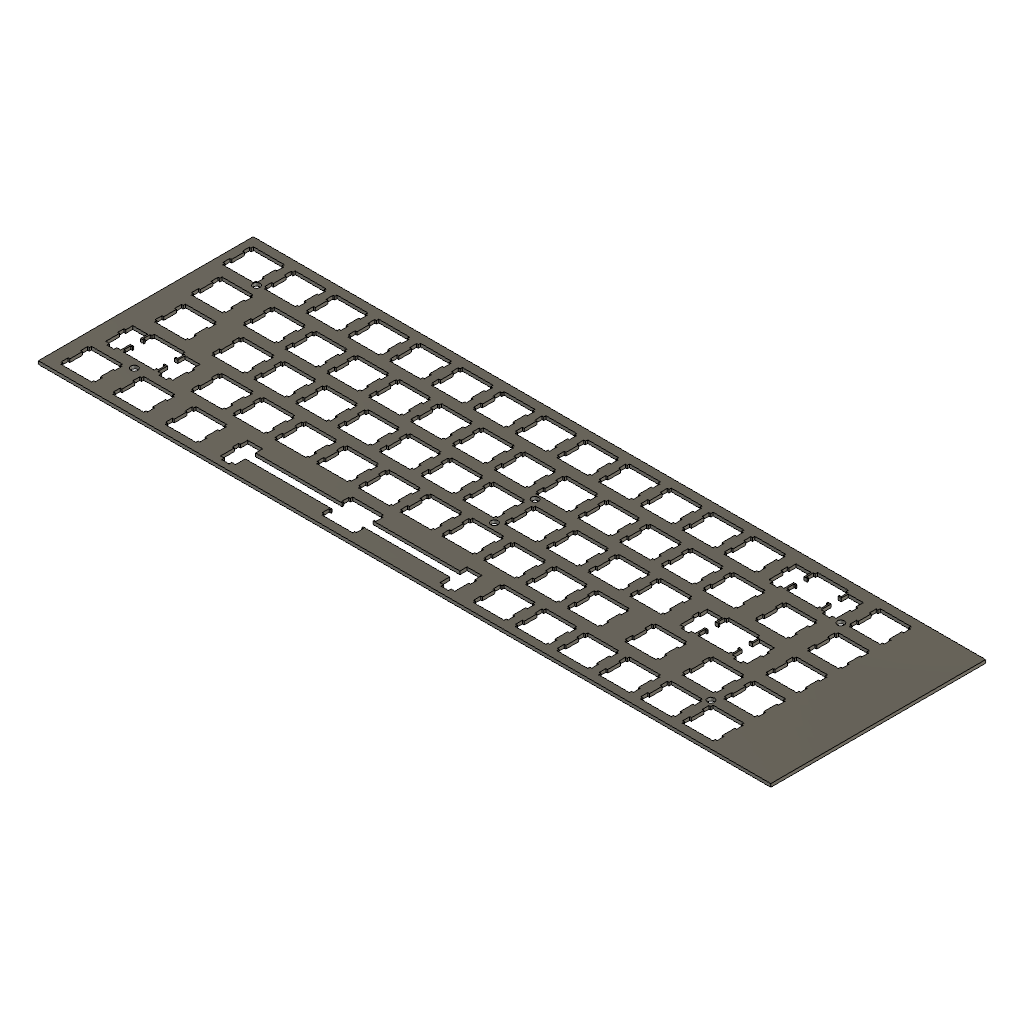
kaze-plate (Autodesk Fusion 360 design; units mm, degrees)
part number: 2026-10-22-08-37-23-062
Autodesk Fusion 360 part; units mm, degrees
(part 1 of 2)
sketch "Sketch1" plane through (0, 0, 0) normal (0, 0, 1) x (1, 0, 0)
  line L0 (-60, 50) -> (274, 50)
  line L1 (274, 50) -> (274, -48)
  line L2 (274, -48) -> (-60, -48)
  line L3 (-60, -48) -> (-60, 50)
  line L4 (65.562, -30.2169) -> (65.562, -31.2173)
  line L5 (65.562, -31.2173) -> (64.763, -31.2173)
  line L6 (64.763, -31.2173) -> (64.763, -34.3152)
  line L7 (64.763, -34.3152) -> (65.562, -34.3152)
  line L8 (65.562, -34.3152) -> (65.562, -34.9174)
  line L9 (65.562, -34.9174) -> (25.9381, -34.9174)
  line L10 (25.9381, -34.9174) -> (25.9381, -31.6872)
  line L11 (25.9381, -31.6872) -> (19.187, -31.6872)
  line L12 (19.187, -31.6872) -> (19.187, -34.9174)
  line L13 (19.187, -34.9174) -> (18.3629, -34.9174)
  line L14 (18.3629, -34.9174) -> (18.3629, -37.7162)
  line L15 (18.3629, -37.7162) -> (19.187, -37.7162)
  line L16 (19.187, -37.7162) -> (19.187, -43.9862)
  line L17 (19.187, -43.9862) -> (20.912, -43.9862)
  line L18 (20.912, -43.9862) -> (20.912, -45.1865)
  line L19 (20.912, -45.1865) -> (24.2126, -45.1865)
  line L20 (24.2126, -45.1865) -> (24.2126, -43.9862)
  line L21 (24.2126, -43.9862) -> (25.9381, -43.9862)
  line L22 (25.9381, -43.9862) -> (25.9381, -39.5159)
  line L23 (25.9381, -39.5159) -> (65.562, -39.5159)
  line L24 (65.562, -39.5159) -> (65.562, -40.1167)
  line L25 (65.562, -40.1167) -> (64.763, -40.1167)
  line L26 (64.763, -40.1167) -> (64.763, -43.2173)
  line L27 (64.763, -43.2173) -> (65.562, -43.2173)
  line L28 (65.562, -43.2173) -> (65.562, -44.2164)
  line L29 (65.562, -44.2164) -> (79.563, -44.2164)
  line L30 (79.563, -44.2164) -> (79.563, -43.2173)
  line L31 (79.563, -43.2173) -> (80.362, -43.2173)
  line L32 (80.362, -43.2173) -> (80.362, -40.1167)
  line L33 (80.362, -40.1167) -> (79.563, -40.1167)
  line L34 (79.563, -40.1167) -> (79.563, -39.5159)
  line L35 (79.563, -39.5159) -> (119.187, -39.5159)
  line L36 (119.187, -39.5159) -> (119.187, -43.9862)
  line L37 (119.187, -43.9862) -> (120.912, -43.9862)
  line L38 (120.912, -43.9862) -> (120.912, -45.1865)
  line L39 (120.912, -45.1865) -> (124.213, -45.1865)
  line L40 (124.213, -45.1865) -> (124.213, -43.9862)
  line L41 (124.213, -43.9862) -> (125.938, -43.9862)
  line L42 (125.938, -43.9862) -> (125.938, -37.7162)
  line L43 (125.938, -37.7162) -> (126.762, -37.7162)
  line L44 (126.762, -37.7162) -> (126.762, -34.9174)
  line L45 (126.762, -34.9174) -> (125.938, -34.9174)
  line L46 (125.938, -34.9174) -> (125.938, -31.6872)
  line L47 (125.938, -31.6872) -> (119.187, -31.6872)
  line L48 (119.187, -31.6872) -> (119.187, -34.9174)
  line L49 (119.187, -34.9174) -> (79.563, -34.9174)
  line L50 (79.563, -34.9174) -> (79.563, -34.3152)
  line L51 (79.563, -34.3152) -> (80.362, -34.3152)
  line L52 (80.362, -34.3152) -> (80.362, -31.2173)
  line L53 (80.362, -31.2173) -> (79.563, -31.2173)
  line L54 (79.563, -31.2173) -> (79.563, -30.2169)
  line L55 (79.563, -30.2169) -> (65.562, -30.2169)
  line L56 (-53.4991, -30.2169) -> (-53.4991, -31.2173)
  line L57 (-53.4991, -31.2173) -> (-54.2997, -31.2173)
  line L58 (-54.2997, -31.2173) -> (-54.2997, -34.3152)
  line L59 (-54.2997, -34.3152) -> (-53.4991, -34.3152)
  line L60 (-53.4991, -34.3152) -> (-53.4991, -40.1167)
  line L61 (-53.4991, -40.1167) -> (-54.2997, -40.1167)
  line L62 (-54.2997, -40.1167) -> (-54.2997, -43.2173)
  line L63 (-54.2997, -43.2173) -> (-53.4991, -43.2173)
  line L64 (-53.4991, -43.2173) -> (-53.4991, -44.2164)
  line L65 (-53.4991, -44.2164) -> (-39.4996, -44.2164)
  line L66 (-39.4996, -44.2164) -> (-39.4996, -43.2173)
  line L67 (-39.4996, -43.2173) -> (-38.699, -43.2173)
  line L68 (-38.699, -43.2173) -> (-38.699, -40.1167)
  line L69 (-38.699, -40.1167) -> (-39.4996, -40.1167)
  line L70 (-39.4996, -40.1167) -> (-39.4996, -34.3152)
  line L71 (-39.4996, -34.3152) -> (-38.699, -34.3152)
  line L72 (-38.699, -34.3152) -> (-38.699, -31.2173)
  line L73 (-38.699, -31.2173) -> (-39.4996, -31.2173)
  line L74 (-39.4996, -31.2173) -> (-39.4996, -30.2169)
  line L75 (-39.4996, -30.2169) -> (-53.4991, -30.2169)
  line L76 (-29.688, -30.2169) -> (-29.688, -31.2173)
  line L77 (-29.688, -31.2173) -> (-30.4872, -31.2173)
  line L78 (-30.4872, -31.2173) -> (-30.4872, -34.3152)
  line L79 (-30.4872, -34.3152) -> (-29.688, -34.3152)
  line L80 (-29.688, -34.3152) -> (-29.688, -40.1167)
  line L81 (-29.688, -40.1167) -> (-30.4872, -40.1167)
  line L82 (-30.4872, -40.1167) -> (-30.4872, -43.2173)
  line L83 (-30.4872, -43.2173) -> (-29.688, -43.2173)
  line L84 (-29.688, -43.2173) -> (-29.688, -44.2164)
  line L85 (-29.688, -44.2164) -> (-15.6872, -44.2164)
  line L86 (-15.6872, -44.2164) -> (-15.6872, -43.2173)
  line L87 (-15.6872, -43.2173) -> (-14.8878, -43.2173)
  line L88 (-14.8878, -43.2173) -> (-14.8878, -40.1167)
  line L89 (-14.8878, -40.1167) -> (-15.6872, -40.1167)
  line L90 (-15.6872, -40.1167) -> (-15.6872, -34.3152)
  line L91 (-15.6872, -34.3152) -> (-14.8878, -34.3152)
  line L92 (-14.8878, -34.3152) -> (-14.8878, -31.2173)
  line L93 (-14.8878, -31.2173) -> (-15.6872, -31.2173)
  line L94 (-15.6872, -31.2173) -> (-15.6872, -30.2169)
  line L95 (-15.6872, -30.2169) -> (-29.688, -30.2169)
  line L96 (-5.874, -30.2169) -> (-5.874, -31.2173)
  line L97 (-5.874, -31.2173) -> (-6.6748, -31.2173)
  line L98 (-6.6748, -31.2173) -> (-6.6748, -34.3152)
  line L99 (-6.6748, -34.3152) -> (-5.874, -34.3152)
  line L100 (-5.874, -34.3152) -> (-5.874, -40.1167)
  line L101 (-5.874, -40.1167) -> (-6.6748, -40.1167)
  line L102 (-6.6748, -40.1167) -> (-6.6748, -43.2173)
  line L103 (-6.6748, -43.2173) -> (-5.874, -43.2173)
  line L104 (-5.874, -43.2173) -> (-5.874, -44.2164)
  line L105 (-5.874, -44.2164) -> (8.1253, -44.2164)
  line L106 (8.1253, -44.2164) -> (8.1253, -43.2173)
  line L107 (8.1253, -43.2173) -> (8.9261, -43.2173)
  line L108 (8.9261, -43.2173) -> (8.9261, -40.1167)
  line L109 (8.9261, -40.1167) -> (8.1253, -40.1167)
  line L110 (8.1253, -40.1167) -> (8.1253, -34.3152)
  line L111 (8.1253, -34.3152) -> (8.9261, -34.3152)
  line L112 (8.9261, -34.3152) -> (8.9261, -31.2173)
  line L113 (8.9261, -31.2173) -> (8.1253, -31.2173)
  line L114 (8.1253, -31.2173) -> (8.1253, -30.2169)
  line L115 (8.1253, -30.2169) -> (-5.874, -30.2169)
  line L116 (134.62, -30.2169) -> (134.62, -31.2173)
  line L117 (134.62, -31.2173) -> (133.819, -31.2173)
  line L118 (133.819, -31.2173) -> (133.819, -34.3152)
  line L119 (133.819, -34.3152) -> (134.62, -34.3152)
  line L120 (134.62, -34.3152) -> (134.62, -40.1167)
  line L121 (134.62, -40.1167) -> (133.819, -40.1167)
  line L122 (133.819, -40.1167) -> (133.819, -43.2173)
  line L123 (133.819, -43.2173) -> (134.62, -43.2173)
  line L124 (134.62, -43.2173) -> (134.62, -44.2164)
  line L125 (134.62, -44.2164) -> (148.619, -44.2164)
  line L126 (148.619, -44.2164) -> (148.619, -43.2173)
  line L127 (148.619, -43.2173) -> (149.42, -43.2173)
  line L128 (149.42, -43.2173) -> (149.42, -40.1167)
  line L129 (149.42, -40.1167) -> (148.619, -40.1167)
  line L130 (148.619, -40.1167) -> (148.619, -34.3152)
  line L131 (148.619, -34.3152) -> (149.42, -34.3152)
  line L132 (149.42, -34.3152) -> (149.42, -31.2173)
  line L133 (149.42, -31.2173) -> (148.619, -31.2173)
  line L134 (148.619, -31.2173) -> (148.619, -30.2169)
  line L135 (148.619, -30.2169) -> (134.62, -30.2169)
  line L136 (153.67, -30.2169) -> (153.67, -31.2173)
  line L137 (153.67, -31.2173) -> (152.869, -31.2173)
  line L138 (152.869, -31.2173) -> (152.869, -34.3152)
  line L139 (152.869, -34.3152) -> (153.67, -34.3152)
  line L140 (153.67, -34.3152) -> (153.67, -40.1167)
  line L141 (153.67, -40.1167) -> (152.869, -40.1167)
  line L142 (152.869, -40.1167) -> (152.869, -43.2173)
  line L143 (152.869, -43.2173) -> (153.67, -43.2173)
  line L144 (153.67, -43.2173) -> (153.67, -44.2164)
  line L145 (153.67, -44.2164) -> (167.669, -44.2164)
  line L146 (167.669, -44.2164) -> (167.669, -43.2173)
  line L147 (167.669, -43.2173) -> (168.47, -43.2173)
  line L148 (168.47, -43.2173) -> (168.47, -40.1167)
  line L149 (168.47, -40.1167) -> (167.669, -40.1167)
  line L150 (167.669, -40.1167) -> (167.669, -34.3152)
  line L151 (167.669, -34.3152) -> (168.47, -34.3152)
  line L152 (168.47, -34.3152) -> (168.47, -31.2173)
  line L153 (168.47, -31.2173) -> (167.669, -31.2173)
  line L154 (167.669, -31.2173) -> (167.669, -30.2169)
  line L155 (167.669, -30.2169) -> (153.67, -30.2169)
  line L156 (172.72, -30.2169) -> (172.72, -31.2173)
  line L157 (172.72, -31.2173) -> (171.919, -31.2173)
  line L158 (171.919, -31.2173) -> (171.919, -34.3152)
  line L159 (171.919, -34.3152) -> (172.72, -34.3152)
  line L160 (172.72, -34.3152) -> (172.72, -40.1167)
  line L161 (172.72, -40.1167) -> (171.919, -40.1167)
  line L162 (171.919, -40.1167) -> (171.919, -43.2173)
  line L163 (171.919, -43.2173) -> (172.72, -43.2173)
  line L164 (172.72, -43.2173) -> (172.72, -44.2164)
  line L165 (172.72, -44.2164) -> (186.719, -44.2164)
  line L166 (186.719, -44.2164) -> (186.719, -43.2173)
  line L167 (186.719, -43.2173) -> (187.52, -43.2173)
  line L168 (187.52, -43.2173) -> (187.52, -40.1167)
  line L169 (187.52, -40.1167) -> (186.719, -40.1167)
  line L170 (186.719, -40.1167) -> (186.719, -34.3152)
  line L171 (186.719, -34.3152) -> (187.52, -34.3152)
  line L172 (187.52, -34.3152) -> (187.52, -31.2173)
  line L173 (187.52, -31.2173) -> (186.719, -31.2173)
  line L174 (186.719, -31.2173) -> (186.719, -30.2169)
  line L175 (186.719, -30.2169) -> (172.72, -30.2169)
  line L176 (191.77, -30.2169) -> (191.77, -31.2173)
  line L177 (191.77, -31.2173) -> (190.969, -31.2173)
  line L178 (190.969, -31.2173) -> (190.969, -34.3152)
  line L179 (190.969, -34.3152) -> (191.77, -34.3152)
  line L180 (191.77, -34.3152) -> (191.77, -40.1167)
  line L181 (191.77, -40.1167) -> (190.969, -40.1167)
  line L182 (190.969, -40.1167) -> (190.969, -43.2173)
  line L183 (190.969, -43.2173) -> (191.77, -43.2173)
  line L184 (191.77, -43.2173) -> (191.77, -44.2164)
  line L185 (191.77, -44.2164) -> (205.769, -44.2164)
  line L186 (205.769, -44.2164) -> (205.769, -43.2173)
  line L187 (205.769, -43.2173) -> (206.57, -43.2173)
  line L188 (206.57, -43.2173) -> (206.57, -40.1167)
  line L189 (206.57, -40.1167) -> (205.769, -40.1167)
  line L190 (205.769, -40.1167) -> (205.769, -34.3152)
  line L191 (205.769, -34.3152) -> (206.57, -34.3152)
  line L192 (206.57, -34.3152) -> (206.57, -31.2173)
  line L193 (206.57, -31.2173) -> (205.769, -31.2173)
  line L194 (205.769, -31.2173) -> (205.769, -30.2169)
  line L195 (205.769, -30.2169) -> (191.77, -30.2169)
  line L196 (210.82, -30.2169) -> (210.82, -31.2173)
  line L197 (210.82, -31.2173) -> (210.019, -31.2173)
  line L198 (210.019, -31.2173) -> (210.019, -34.3152)
  line L199 (210.019, -34.3152) -> (210.82, -34.3152)
  line L200 (210.82, -34.3152) -> (210.82, -40.1167)
  line L201 (210.82, -40.1167) -> (210.019, -40.1167)
  line L202 (210.019, -40.1167) -> (210.019, -43.2173)
  line L203 (210.019, -43.2173) -> (210.82, -43.2173)
  line L204 (210.82, -43.2173) -> (210.82, -44.2164)
  line L205 (210.82, -44.2164) -> (224.819, -44.2164)
  line L206 (224.819, -44.2164) -> (224.819, -43.2173)
  line L207 (224.819, -43.2173) -> (225.62, -43.2173)
  line L208 (225.62, -43.2173) -> (225.62, -40.1167)
  line L209 (225.62, -40.1167) -> (224.819, -40.1167)
  line L210 (224.819, -40.1167) -> (224.819, -34.3152)
  line L211 (224.819, -34.3152) -> (225.62, -34.3152)
  line L212 (225.62, -34.3152) -> (225.62, -31.2173)
  line L213 (225.62, -31.2173) -> (224.819, -31.2173)
  line L214 (224.819, -31.2173) -> (224.819, -30.2169)
  line L215 (224.819, -30.2169) -> (210.82, -30.2169)
  line L216 (229.87, -30.2169) -> (229.87, -31.2173)
  line L217 (229.87, -31.2173) -> (229.069, -31.2173)
  line L218 (229.069, -31.2173) -> (229.069, -34.3152)
  line L219 (229.069, -34.3152) -> (229.87, -34.3152)
  line L220 (229.87, -34.3152) -> (229.87, -40.1167)
  line L221 (229.87, -40.1167) -> (229.069, -40.1167)
  line L222 (229.069, -40.1167) -> (229.069, -43.2173)
  line L223 (229.069, -43.2173) -> (229.87, -43.2173)
  line L224 (229.87, -43.2173) -> (229.87, -44.2164)
  line L225 (229.87, -44.2164) -> (243.869, -44.2164)
  line L226 (243.869, -44.2164) -> (243.869, -43.2173)
  line L227 (243.869, -43.2173) -> (244.67, -43.2173)
  line L228 (244.67, -43.2173) -> (244.67, -40.1167)
  line L229 (244.67, -40.1167) -> (243.869, -40.1167)
  line L230 (243.869, -40.1167) -> (243.869, -34.3152)
  line L231 (243.869, -34.3152) -> (244.67, -34.3152)
  line L232 (244.67, -34.3152) -> (244.67, -31.2173)
  line L233 (244.67, -31.2173) -> (243.869, -31.2173)
  line L234 (243.869, -31.2173) -> (243.869, -30.2169)
  line L235 (243.869, -30.2169) -> (229.87, -30.2169)
  line L236 (-43.9741, -11.167) -> (-43.9741, -12.1673)
  line L237 (-43.9741, -12.1673) -> (-44.7747, -12.1673)
  line L238 (-44.7747, -12.1673) -> (-44.7747, -15.2652)
  line L239 (-44.7747, -15.2652) -> (-43.9741, -15.2652)
  line L240 (-43.9741, -15.2652) -> (-43.9741, -15.8674)
  line L241 (-43.9741, -15.8674) -> (-45.4996, -15.8674)
  line L242 (-45.4996, -15.8674) -> (-45.4996, -12.6372)
  line L243 (-45.4996, -12.6372) -> (-52.2492, -12.6372)
  line L244 (-52.2492, -12.6372) -> (-52.2492, -15.8674)
  line L245 (-52.2492, -15.8674) -> (-53.0747, -15.8674)
  line L246 (-53.0747, -15.8674) -> (-53.0747, -18.6662)
  line L247 (-53.0747, -18.6662) -> (-52.2492, -18.6662)
  line L248 (-52.2492, -18.6662) -> (-52.2492, -24.9362)
  line L249 (-52.2492, -24.9362) -> (-50.5239, -24.9362)
  line L250 (-50.5239, -24.9362) -> (-50.5239, -26.1365)
  line L251 (-50.5239, -26.1365) -> (-47.2249, -26.1365)
  line L252 (-47.2249, -26.1365) -> (-47.2249, -24.9362)
  line L253 (-47.2249, -24.9362) -> (-45.4996, -24.9362)
  line L254 (-45.4996, -24.9362) -> (-45.4996, -20.4673)
  line L255 (-45.4996, -20.4673) -> (-43.9741, -20.4673)
  line L256 (-43.9741, -20.4673) -> (-43.9741, -21.0667)
  line L257 (-43.9741, -21.0667) -> (-44.7747, -21.0667)
  line L258 (-44.7747, -21.0667) -> (-44.7747, -24.1673)
  line L259 (-44.7747, -24.1673) -> (-43.9741, -24.1673)
  line L260 (-43.9741, -24.1673) -> (-43.9741, -25.1664)
  line L261 (-43.9741, -25.1664) -> (-29.9746, -25.1664)
  line L262 (-29.9746, -25.1664) -> (-29.9746, -24.1673)
  line L263 (-29.9746, -24.1673) -> (-29.174, -24.1673)
  line L264 (-29.174, -24.1673) -> (-29.174, -21.0667)
  line L265 (-29.174, -21.0667) -> (-29.9746, -21.0667)
  line L266 (-29.9746, -21.0667) -> (-29.9746, -20.4673)
  line L267 (-29.9746, -20.4673) -> (-28.4491, -20.4673)
  line L268 (-28.4491, -20.4673) -> (-28.4491, -24.9362)
  line L269 (-28.4491, -24.9362) -> (-26.7252, -24.9362)
  line L270 (-26.7252, -24.9362) -> (-26.7252, -26.1365)
  line L271 (-26.7252, -26.1365) -> (-23.4248, -26.1365)
  line L272 (-23.4248, -26.1365) -> (-23.4248, -24.9362)
  line L273 (-23.4248, -24.9362) -> (-21.6996, -24.9362)
  line L274 (-21.6996, -24.9362) -> (-21.6996, -18.6662)
  line L275 (-21.6996, -18.6662) -> (-20.8741, -18.6662)
  line L276 (-20.8741, -18.6662) -> (-20.8741, -15.8674)
  line L277 (-20.8741, -15.8674) -> (-21.6996, -15.8674)
  line L278 (-21.6996, -15.8674) -> (-21.6996, -12.6372)
  line L279 (-21.6996, -12.6372) -> (-28.4491, -12.6372)
  line L280 (-28.4491, -12.6372) -> (-28.4491, -15.8674)
  line L281 (-28.4491, -15.8674) -> (-29.9746, -15.8674)
  line L282 (-29.9746, -15.8674) -> (-29.9746, -15.2652)
  line L283 (-29.9746, -15.2652) -> (-29.174, -15.2652)
  line L284 (-29.174, -15.2652) -> (-29.174, -12.1673)
  line L285 (-29.174, -12.1673) -> (-29.9746, -12.1673)
  line L286 (-29.9746, -12.1673) -> (-29.9746, -11.167)
  line L287 (-29.9746, -11.167) -> (-43.9741, -11.167)
  line L288 (-13.0178, -11.167) -> (-13.0178, -12.1673)
  line L289 (-13.0178, -12.1673) -> (-13.8186, -12.1673)
  line L290 (-13.8186, -12.1673) -> (-13.8186, -15.2652)
  line L291 (-13.8186, -15.2652) -> (-13.0178, -15.2652)
  line L292 (-13.0178, -15.2652) -> (-13.0178, -21.0667)
  line L293 (-13.0178, -21.0667) -> (-13.8186, -21.0667)
  line L294 (-13.8186, -21.0667) -> (-13.8186, -24.1673)
  line L295 (-13.8186, -24.1673) -> (-13.0178, -24.1673)
  line L296 (-13.0178, -24.1673) -> (-13.0178, -25.1664)
  line L297 (-13.0178, -25.1664) -> (0.9815, -25.1664)
  line L298 (0.9815, -25.1664) -> (0.9815, -24.1673)
  line L299 (0.9815, -24.1673) -> (1.7809, -24.1673)
  line L300 (1.7809, -24.1673) -> (1.7809, -21.0667)
  line L301 (1.7809, -21.0667) -> (0.9815, -21.0667)
  line L302 (0.9815, -21.0667) -> (0.9815, -15.2652)
  line L303 (0.9815, -15.2652) -> (1.7809, -15.2652)
  line L304 (1.7809, -15.2652) -> (1.7809, -12.1673)
  line L305 (1.7809, -12.1673) -> (0.9815, -12.1673)
  line L306 (0.9815, -12.1673) -> (0.9815, -11.167)
  line L307 (0.9815, -11.167) -> (-13.0178, -11.167)
  line L308 (6.0322, -11.167) -> (6.0322, -12.1673)
  line L309 (6.0322, -12.1673) -> (5.2314, -12.1673)
  line L310 (5.2314, -12.1673) -> (5.2314, -15.2652)
  line L311 (5.2314, -15.2652) -> (6.0322, -15.2652)
  line L312 (6.0322, -15.2652) -> (6.0322, -21.0667)
  line L313 (6.0322, -21.0667) -> (5.2314, -21.0667)
  line L314 (5.2314, -21.0667) -> (5.2314, -24.1673)
  line L315 (5.2314, -24.1673) -> (6.0322, -24.1673)
  line L316 (6.0322, -24.1673) -> (6.0322, -25.1664)
  line L317 (6.0322, -25.1664) -> (20.0315, -25.1664)
  line L318 (20.0315, -25.1664) -> (20.0315, -24.1673)
  line L319 (20.0315, -24.1673) -> (20.8309, -24.1673)
  line L320 (20.8309, -24.1673) -> (20.8309, -21.0667)
  line L321 (20.8309, -21.0667) -> (20.0315, -21.0667)
  line L322 (20.0315, -21.0667) -> (20.0315, -15.2652)
  line L323 (20.0315, -15.2652) -> (20.8309, -15.2652)
  line L324 (20.8309, -15.2652) -> (20.8309, -12.1673)
  line L325 (20.8309, -12.1673) -> (20.0315, -12.1673)
  line L326 (20.0315, -12.1673) -> (20.0315, -11.167)
  line L327 (20.0315, -11.167) -> (6.0322, -11.167)
  line L328 (25.0822, -11.167) -> (25.0822, -12.1673)
  line L329 (25.0822, -12.1673) -> (24.2814, -12.1673)
  line L330 (24.2814, -12.1673) -> (24.2814, -15.2652)
  line L331 (24.2814, -15.2652) -> (25.0822, -15.2652)
  line L332 (25.0822, -15.2652) -> (25.0822, -21.0667)
  line L333 (25.0822, -21.0667) -> (24.2814, -21.0667)
  line L334 (24.2814, -21.0667) -> (24.2814, -24.1673)
  line L335 (24.2814, -24.1673) -> (25.0822, -24.1673)
  line L336 (25.0822, -24.1673) -> (25.0822, -25.1664)
  line L337 (25.0822, -25.1664) -> (39.0815, -25.1664)
  line L338 (39.0815, -25.1664) -> (39.0815, -24.1673)
  line L339 (39.0815, -24.1673) -> (39.8809, -24.1673)
  line L340 (39.8809, -24.1673) -> (39.8809, -21.0667)
  line L341 (39.8809, -21.0667) -> (39.0815, -21.0667)
  line L342 (39.0815, -21.0667) -> (39.0815, -15.2652)
  line L343 (39.0815, -15.2652) -> (39.8809, -15.2652)
  line L344 (39.8809, -15.2652) -> (39.8809, -12.1673)
  line L345 (39.8809, -12.1673) -> (39.0815, -12.1673)
  line L346 (39.0815, -12.1673) -> (39.0815, -11.167)
  line L347 (39.0815, -11.167) -> (25.0822, -11.167)
  line L348 (44.132, -11.167) -> (44.132, -12.1673)
  line L349 (44.132, -12.1673) -> (43.331, -12.1673)
  line L350 (43.331, -12.1673) -> (43.331, -15.2652)
  line L351 (43.331, -15.2652) -> (44.132, -15.2652)
  line L352 (44.132, -15.2652) -> (44.132, -21.0667)
  line L353 (44.132, -21.0667) -> (43.331, -21.0667)
  line L354 (43.331, -21.0667) -> (43.331, -24.1673)
  line L355 (43.331, -24.1673) -> (44.132, -24.1673)
  line L356 (44.132, -24.1673) -> (44.132, -25.1664)
  line L357 (44.132, -25.1664) -> (58.132, -25.1664)
  line L358 (58.132, -25.1664) -> (58.132, -24.1673)
  line L359 (58.132, -24.1673) -> (58.931, -24.1673)
  line L360 (58.931, -24.1673) -> (58.931, -21.0667)
  line L361 (58.931, -21.0667) -> (58.132, -21.0667)
  line L362 (58.132, -21.0667) -> (58.132, -15.2652)
  line L363 (58.132, -15.2652) -> (58.931, -15.2652)
  line L364 (58.931, -15.2652) -> (58.931, -12.1673)
  line L365 (58.931, -12.1673) -> (58.132, -12.1673)
  line L366 (58.132, -12.1673) -> (58.132, -11.167)
  line L367 (58.132, -11.167) -> (44.132, -11.167)
  line L368 (63.182, -11.167) -> (63.182, -12.1673)
  line L369 (63.182, -12.1673) -> (62.381, -12.1673)
  line L370 (62.381, -12.1673) -> (62.381, -15.2652)
  line L371 (62.381, -15.2652) -> (63.182, -15.2652)
  line L372 (63.182, -15.2652) -> (63.182, -21.0667)
  line L373 (63.182, -21.0667) -> (62.381, -21.0667)
  line L374 (62.381, -21.0667) -> (62.381, -24.1673)
  line L375 (62.381, -24.1673) -> (63.182, -24.1673)
  line L376 (63.182, -24.1673) -> (63.182, -25.1664)
  line L377 (63.182, -25.1664) -> (77.182, -25.1664)
  line L378 (77.182, -25.1664) -> (77.182, -24.1673)
  line L379 (77.182, -24.1673) -> (77.981, -24.1673)
  line L380 (77.981, -24.1673) -> (77.981, -21.0667)
  line L381 (77.981, -21.0667) -> (77.182, -21.0667)
  line L382 (77.182, -21.0667) -> (77.182, -15.2652)
  line L383 (77.182, -15.2652) -> (77.981, -15.2652)
  line L384 (77.981, -15.2652) -> (77.981, -12.1673)
  line L385 (77.981, -12.1673) -> (77.182, -12.1673)
  line L386 (77.182, -12.1673) -> (77.182, -11.167)
  line L387 (77.182, -11.167) -> (63.182, -11.167)
  line L388 (82.232, -11.167) -> (82.232, -12.1673)
  line L389 (82.232, -12.1673) -> (81.431, -12.1673)
  line L390 (81.431, -12.1673) -> (81.431, -15.2652)
  line L391 (81.431, -15.2652) -> (82.232, -15.2652)
  line L392 (82.232, -15.2652) -> (82.232, -21.0667)
  line L393 (82.232, -21.0667) -> (81.431, -21.0667)
  line L394 (81.431, -21.0667) -> (81.431, -24.1673)
  line L395 (81.431, -24.1673) -> (82.232, -24.1673)
  line L396 (82.232, -24.1673) -> (82.232, -25.1664)
  line L397 (82.232, -25.1664) -> (96.232, -25.1664)
  line L398 (96.232, -25.1664) -> (96.232, -24.1673)
  line L399 (96.232, -24.1673) -> (97.031, -24.1673)
  line L400 (97.031, -24.1673) -> (97.031, -21.0667)
  line L401 (97.031, -21.0667) -> (96.232, -21.0667)
  line L402 (96.232, -21.0667) -> (96.232, -15.2652)
  line L403 (96.232, -15.2652) -> (97.031, -15.2652)
  line L404 (97.031, -15.2652) -> (97.031, -12.1673)
  line L405 (97.031, -12.1673) -> (96.232, -12.1673)
  line L406 (96.232, -12.1673) -> (96.232, -11.167)
  line L407 (96.232, -11.167) -> (82.232, -11.167)
  line L408 (101.282, -11.167) -> (101.282, -12.1673)
  line L409 (101.282, -12.1673) -> (100.481, -12.1673)
  line L410 (100.481, -12.1673) -> (100.481, -15.2652)
  line L411 (100.481, -15.2652) -> (101.282, -15.2652)
  line L412 (101.282, -15.2652) -> (101.282, -21.0667)
  line L413 (101.282, -21.0667) -> (100.481, -21.0667)
  line L414 (100.481, -21.0667) -> (100.481, -24.1673)
  line L415 (100.481, -24.1673) -> (101.282, -24.1673)
  line L416 (101.282, -24.1673) -> (101.282, -25.1664)
  line L417 (101.282, -25.1664) -> (115.282, -25.1664)
  line L418 (115.282, -25.1664) -> (115.282, -24.1673)
  line L419 (115.282, -24.1673) -> (116.081, -24.1673)
  line L420 (116.081, -24.1673) -> (116.081, -21.0667)
  line L421 (116.081, -21.0667) -> (115.282, -21.0667)
  line L422 (115.282, -21.0667) -> (115.282, -15.2652)
  line L423 (115.282, -15.2652) -> (116.081, -15.2652)
  line L424 (116.081, -15.2652) -> (116.081, -12.1673)
  line L425 (116.081, -12.1673) -> (115.282, -12.1673)
  line L426 (115.282, -12.1673) -> (115.282, -11.167)
  line L427 (115.282, -11.167) -> (101.282, -11.167)
  line L428 (120.332, -11.167) -> (120.332, -12.1673)
  line L429 (120.332, -12.1673) -> (119.531, -12.1673)
  line L430 (119.531, -12.1673) -> (119.531, -15.2652)
  line L431 (119.531, -15.2652) -> (120.332, -15.2652)
  line L432 (120.332, -15.2652) -> (120.332, -21.0667)
  line L433 (120.332, -21.0667) -> (119.531, -21.0667)
  line L434 (119.531, -21.0667) -> (119.531, -24.1673)
  line L435 (119.531, -24.1673) -> (120.332, -24.1673)
  line L436 (120.332, -24.1673) -> (120.332, -25.1664)
  line L437 (120.332, -25.1664) -> (134.332, -25.1664)
  line L438 (134.332, -25.1664) -> (134.332, -24.1673)
  line L439 (134.332, -24.1673) -> (135.131, -24.1673)
  line L440 (135.131, -24.1673) -> (135.131, -21.0667)
  line L441 (135.131, -21.0667) -> (134.332, -21.0667)
  line L442 (134.332, -21.0667) -> (134.332, -15.2652)
  line L443 (134.332, -15.2652) -> (135.131, -15.2652)
  line L444 (135.131, -15.2652) -> (135.131, -12.1673)
  line L445 (135.131, -12.1673) -> (134.332, -12.1673)
  line L446 (134.332, -12.1673) -> (134.332, -11.167)
  line L447 (134.332, -11.167) -> (120.332, -11.167)
  line L448 (139.382, -11.167) -> (139.382, -12.1673)
  line L449 (139.382, -12.1673) -> (138.581, -12.1673)
  line L450 (138.581, -12.1673) -> (138.581, -15.2652)
  line L451 (138.581, -15.2652) -> (139.382, -15.2652)
  line L452 (139.382, -15.2652) -> (139.382, -21.0667)
  line L453 (139.382, -21.0667) -> (138.581, -21.0667)
  line L454 (138.581, -21.0667) -> (138.581, -24.1673)
  line L455 (138.581, -24.1673) -> (139.382, -24.1673)
  line L456 (139.382, -24.1673) -> (139.382, -25.1664)
  line L457 (139.382, -25.1664) -> (153.382, -25.1664)
  line L458 (153.382, -25.1664) -> (153.382, -24.1673)
  line L459 (153.382, -24.1673) -> (154.181, -24.1673)
  line L460 (154.181, -24.1673) -> (154.181, -21.0667)
  line L461 (154.181, -21.0667) -> (153.382, -21.0667)
  line L462 (153.382, -21.0667) -> (153.382, -15.2652)
  line L463 (153.382, -15.2652) -> (154.181, -15.2652)
  line L464 (154.181, -15.2652) -> (154.181, -12.1673)
  line L465 (154.181, -12.1673) -> (153.382, -12.1673)
  line L466 (153.382, -12.1673) -> (153.382, -11.167)
  line L467 (153.382, -11.167) -> (139.382, -11.167)
  line L468 (158.432, -11.167) -> (158.432, -12.1673)
  line L469 (158.432, -12.1673) -> (157.631, -12.1673)
  line L470 (157.631, -12.1673) -> (157.631, -15.2652)
  line L471 (157.631, -15.2652) -> (158.432, -15.2652)
  line L472 (158.432, -15.2652) -> (158.432, -21.0667)
  line L473 (158.432, -21.0667) -> (157.631, -21.0667)
  line L474 (157.631, -21.0667) -> (157.631, -24.1673)
  line L475 (157.631, -24.1673) -> (158.432, -24.1673)
  line L476 (158.432, -24.1673) -> (158.432, -25.1664)
  line L477 (158.432, -25.1664) -> (172.432, -25.1664)
  line L478 (172.432, -25.1664) -> (172.432, -24.1673)
  line L479 (172.432, -24.1673) -> (173.231, -24.1673)
  line L480 (173.231, -24.1673) -> (173.231, -21.0667)
  line L481 (173.231, -21.0667) -> (172.432, -21.0667)
  line L482 (172.432, -21.0667) -> (172.432, -15.2652)
  line L483 (172.432, -15.2652) -> (173.231, -15.2652)
  line L484 (173.231, -15.2652) -> (173.231, -12.1673)
  line L485 (173.231, -12.1673) -> (172.432, -12.1673)
  line L486 (172.432, -12.1673) -> (172.432, -11.167)
  line L487 (172.432, -11.167) -> (158.432, -11.167)
  line L488 (184.721, -11.167) -> (184.721, -12.1673)
  line L489 (184.721, -12.1673) -> (183.92, -12.1673)
  line L490 (183.92, -12.1673) -> (183.92, -15.2652)
  line L491 (183.92, -15.2652) -> (184.721, -15.2652)
  line L492 (184.721, -15.2652) -> (184.721, -21.0667)
  line L493 (184.721, -21.0667) -> (183.92, -21.0667)
  line L494 (183.92, -21.0667) -> (183.92, -24.1673)
  line L495 (183.92, -24.1673) -> (184.721, -24.1673)
  line L496 (184.721, -24.1673) -> (184.721, -25.1664)
  line L497 (184.721, -25.1664) -> (198.719, -25.1664)
  line L498 (198.719, -25.1664) -> (198.719, -24.1673)
  line L499 (198.719, -24.1673) -> (199.521, -24.1673)
  line L500 (199.521, -24.1673) -> (199.521, -21.0667)
  line L501 (199.521, -21.0667) -> (198.719, -21.0667)
  line L502 (198.719, -21.0667) -> (198.719, -15.2652)
  line L503 (198.719, -15.2652) -> (199.521, -15.2652)
  line L504 (199.521, -15.2652) -> (199.521, -12.1673)
  line L505 (199.521, -12.1673) -> (198.719, -12.1673)
  line L506 (198.719, -12.1673) -> (198.719, -11.167)
  line L507 (198.719, -11.167) -> (184.721, -11.167)
  line L508 (210.82, -11.167) -> (210.82, -12.1673)
  line L509 (210.82, -12.1673) -> (210.019, -12.1673)
  line L510 (210.019, -12.1673) -> (210.019, -15.2652)
  line L511 (210.019, -15.2652) -> (210.82, -15.2652)
  line L512 (210.82, -15.2652) -> (210.82, -21.0667)
  line L513 (210.82, -21.0667) -> (210.019, -21.0667)
  line L514 (210.019, -21.0667) -> (210.019, -24.1673)
  line L515 (210.019, -24.1673) -> (210.82, -24.1673)
  line L516 (210.82, -24.1673) -> (210.82, -25.1664)
  line L517 (210.82, -25.1664) -> (224.819, -25.1664)
  line L518 (224.819, -25.1664) -> (224.819, -24.1673)
  line L519 (224.819, -24.1673) -> (225.62, -24.1673)
  line L520 (225.62, -24.1673) -> (225.62, -21.0667)
  line L521 (225.62, -21.0667) -> (224.819, -21.0667)
  line L522 (224.819, -21.0667) -> (224.819, -15.2652)
  line L523 (224.819, -15.2652) -> (225.62, -15.2652)
  line L524 (225.62, -15.2652) -> (225.62, -12.1673)
  line L525 (225.62, -12.1673) -> (224.819, -12.1673)
  line L526 (224.819, -12.1673) -> (224.819, -11.167)
  line L527 (224.819, -11.167) -> (210.82, -11.167)
  line L528 (229.87, -11.167) -> (229.87, -12.1673)
  line L529 (229.87, -12.1673) -> (229.069, -12.1673)
  line L530 (229.069, -12.1673) -> (229.069, -15.2652)
  line L531 (229.069, -15.2652) -> (229.87, -15.2652)
  line L532 (229.87, -15.2652) -> (229.87, -21.0667)
  line L533 (229.87, -21.0667) -> (229.069, -21.0667)
  line L534 (229.069, -21.0667) -> (229.069, -24.1673)
  line L535 (229.069, -24.1673) -> (229.87, -24.1673)
  line L536 (229.87, -24.1673) -> (229.87, -25.1664)
  line L537 (229.87, -25.1664) -> (243.869, -25.1664)
  line L538 (243.869, -25.1664) -> (243.869, -24.1673)
  line L539 (243.869, -24.1673) -> (244.67, -24.1673)
  line L540 (244.67, -24.1673) -> (244.67, -21.0667)
  line L541 (244.67, -21.0667) -> (243.869, -21.0667)
  line L542 (243.869, -21.0667) -> (243.869, -15.2652)
  line L543 (243.869, -15.2652) -> (244.67, -15.2652)
  line L544 (244.67, -15.2652) -> (244.67, -12.1673)
  line L545 (244.67, -12.1673) -> (243.869, -12.1673)
  line L546 (243.869, -12.1673) -> (243.869, -11.167)
  line L547 (243.869, -11.167) -> (229.87, -11.167)
  line L548 (198.912, 7.8831) -> (198.912, 6.8826)
  line L549 (198.912, 6.8826) -> (198.111, 6.8826)
  line L550 (198.111, 6.8826) -> (198.111, 3.7834)
  line L551 (198.111, 3.7834) -> (198.912, 3.7834)
  line L552 (198.912, 3.7834) -> (198.912, 3.1826)
  line L553 (198.912, 3.1826) -> (197.388, 3.1826)
  line L554 (197.388, 3.1826) -> (197.388, 6.4127)
  line L555 (197.388, 6.4127) -> (190.637, 6.4127)
  line L556 (190.637, 6.4127) -> (190.637, 3.1826)
  line L557 (190.637, 3.1826) -> (189.813, 3.1826)
  line L558 (189.813, 3.1826) -> (189.813, 0.3837)
  line L559 (189.813, 0.3837) -> (190.637, 0.3837)
  line L560 (190.637, 0.3837) -> (190.637, -5.8862)
  line L561 (190.637, -5.8862) -> (192.362, -5.8862)
  line L562 (192.362, -5.8862) -> (192.362, -7.0864)
  line L563 (192.362, -7.0864) -> (195.661, -7.0864)
  line L564 (195.661, -7.0864) -> (195.661, -5.8862)
  line L565 (195.661, -5.8862) -> (197.388, -5.8862)
  line L566 (197.388, -5.8862) -> (197.388, -1.4172)
  line L567 (197.388, -1.4172) -> (198.912, -1.4172)
  line L568 (198.912, -1.4172) -> (198.912, -2.0166)
  line L569 (198.912, -2.0166) -> (198.111, -2.0166)
  line L570 (198.111, -2.0166) -> (198.111, -5.1172)
  line L571 (198.111, -5.1172) -> (198.912, -5.1172)
  line L572 (198.912, -5.1172) -> (198.912, -6.1162)
  line L573 (198.912, -6.1162) -> (212.913, -6.1162)
  line L574 (212.913, -6.1162) -> (212.913, -5.1172)
  line L575 (212.913, -5.1172) -> (213.712, -5.1172)
  line L576 (213.712, -5.1172) -> (213.712, -2.0166)
  line L577 (213.712, -2.0166) -> (212.913, -2.0166)
  line L578 (212.913, -2.0166) -> (212.913, -1.4172)
  line L579 (212.913, -1.4172) -> (214.437, -1.4172)
  line L580 (214.437, -1.4172) -> (214.437, -5.8862)
  line L581 (214.437, -5.8862) -> (216.162, -5.8862)
  line L582 (216.162, -5.8862) -> (216.162, -7.0864)
  line L583 (216.162, -7.0864) -> (219.463, -7.0864)
  line L584 (219.463, -7.0864) -> (219.463, -5.8862)
  line L585 (219.463, -5.8862) -> (221.188, -5.8862)
  line L586 (221.188, -5.8862) -> (221.188, 0.3837)
  line L587 (221.188, 0.3837) -> (222.012, 0.3837)
  line L588 (222.012, 0.3837) -> (222.012, 3.1826)
  line L589 (222.012, 3.1826) -> (221.188, 3.1826)
  line L590 (221.188, 3.1826) -> (221.188, 6.4127)
  line L591 (221.188, 6.4127) -> (214.437, 6.4127)
  line L592 (214.437, 6.4127) -> (214.437, 3.1826)
  line L593 (214.437, 3.1826) -> (212.913, 3.1826)
  line L594 (212.913, 3.1826) -> (212.913, 3.7834)
  line L595 (212.913, 3.7834) -> (213.712, 3.7834)
  line L596 (213.712, 3.7834) -> (213.712, 6.8826)
  line L597 (213.712, 6.8826) -> (212.913, 6.8826)
  line L598 (212.913, 6.8826) -> (212.913, 7.8831)
  line L599 (212.913, 7.8831) -> (198.912, 7.8831)
  line L600 (-48.738, 7.8831) -> (-48.738, 6.8826)
  line L601 (-48.738, 6.8826) -> (-49.5372, 6.8826)
  line L602 (-49.5372, 6.8826) -> (-49.5372, 3.7834)
  line L603 (-49.5372, 3.7834) -> (-48.738, 3.7834)
  line L604 (-48.738, 3.7834) -> (-48.738, -2.0166)
  line L605 (-48.738, -2.0166) -> (-49.5372, -2.0166)
  line L606 (-49.5372, -2.0166) -> (-49.5372, -5.1172)
  line L607 (-49.5372, -5.1172) -> (-48.738, -5.1172)
  line L608 (-48.738, -5.1172) -> (-48.738, -6.1162)
  line L609 (-48.738, -6.1162) -> (-34.7371, -6.1162)
  line L610 (-34.7371, -6.1162) -> (-34.7371, -5.1172)
  line L611 (-34.7371, -5.1172) -> (-33.9378, -5.1172)
  line L612 (-33.9378, -5.1172) -> (-33.9378, -2.0166)
  line L613 (-33.9378, -2.0166) -> (-34.7371, -2.0166)
  line L614 (-34.7371, -2.0166) -> (-34.7371, 3.7834)
  line L615 (-34.7371, 3.7834) -> (-33.9378, 3.7834)
  line L616 (-33.9378, 3.7834) -> (-33.9378, 6.8826)
  line L617 (-33.9378, 6.8826) -> (-34.7371, 6.8826)
  line L618 (-34.7371, 6.8826) -> (-34.7371, 7.8831)
  line L619 (-34.7371, 7.8831) -> (-48.738, 7.8831)
  line L620 (-22.5428, 7.8831) -> (-22.5428, 6.8826)
  line L621 (-22.5428, 6.8826) -> (-23.3435, 6.8826)
  line L622 (-23.3435, 6.8826) -> (-23.3435, 3.7834)
  line L623 (-23.3435, 3.7834) -> (-22.5428, 3.7834)
  line L624 (-22.5428, 3.7834) -> (-22.5428, -2.0166)
  line L625 (-22.5428, -2.0166) -> (-23.3435, -2.0166)
  line L626 (-23.3435, -2.0166) -> (-23.3435, -5.1172)
  line L627 (-23.3435, -5.1172) -> (-22.5428, -5.1172)
  line L628 (-22.5428, -5.1172) -> (-22.5428, -6.1162)
  line L629 (-22.5428, -6.1162) -> (-8.5435, -6.1162)
  line L630 (-8.5435, -6.1162) -> (-8.5435, -5.1172)
  line L631 (-8.5435, -5.1172) -> (-7.7441, -5.1172)
  line L632 (-7.7441, -5.1172) -> (-7.7441, -2.0166)
  line L633 (-7.7441, -2.0166) -> (-8.5435, -2.0166)
  line L634 (-8.5435, -2.0166) -> (-8.5435, 3.7834)
  line L635 (-8.5435, 3.7834) -> (-7.7441, 3.7834)
  line L636 (-7.7441, 3.7834) -> (-7.7441, 6.8826)
  line L637 (-7.7441, 6.8826) -> (-8.5435, 6.8826)
  line L638 (-8.5435, 6.8826) -> (-8.5435, 7.8831)
  line L639 (-8.5435, 7.8831) -> (-22.5428, 7.8831)
  line L640 (-3.4928, 7.8831) -> (-3.4928, 6.8826)
  line L641 (-3.4928, 6.8826) -> (-4.2936, 6.8826)
  line L642 (-4.2936, 6.8826) -> (-4.2936, 3.7834)
  line L643 (-4.2936, 3.7834) -> (-3.4928, 3.7834)
  line L644 (-3.4928, 3.7834) -> (-3.4928, -2.0166)
  line L645 (-3.4928, -2.0166) -> (-4.2936, -2.0166)
  line L646 (-4.2936, -2.0166) -> (-4.2936, -5.1172)
  line L647 (-4.2936, -5.1172) -> (-3.4928, -5.1172)
  line L648 (-3.4928, -5.1172) -> (-3.4928, -6.1162)
  line L649 (-3.4928, -6.1162) -> (10.5065, -6.1162)
  line L650 (10.5065, -6.1162) -> (10.5065, -5.1172)
  line L651 (10.5065, -5.1172) -> (11.3059, -5.1172)
  line L652 (11.3059, -5.1172) -> (11.3059, -2.0166)
  line L653 (11.3059, -2.0166) -> (10.5065, -2.0166)
  line L654 (10.5065, -2.0166) -> (10.5065, 3.7834)
  line L655 (10.5065, 3.7834) -> (11.3059, 3.7834)
  line L656 (11.3059, 3.7834) -> (11.3059, 6.8826)
  line L657 (11.3059, 6.8826) -> (10.5065, 6.8826)
  line L658 (10.5065, 6.8826) -> (10.5065, 7.8831)
  line L659 (10.5065, 7.8831) -> (-3.4928, 7.8831)
  line L660 (15.5572, 7.8831) -> (15.5572, 6.8826)
  line L661 (15.5572, 6.8826) -> (14.7564, 6.8826)
  line L662 (14.7564, 6.8826) -> (14.7564, 3.7834)
  line L663 (14.7564, 3.7834) -> (15.5572, 3.7834)
  line L664 (15.5572, 3.7834) -> (15.5572, -2.0166)
  line L665 (15.5572, -2.0166) -> (14.7564, -2.0166)
  line L666 (14.7564, -2.0166) -> (14.7564, -5.1172)
  line L667 (14.7564, -5.1172) -> (15.5572, -5.1172)
  line L668 (15.5572, -5.1172) -> (15.5572, -6.1162)
  line L669 (15.5572, -6.1162) -> (29.5565, -6.1162)
  line L670 (29.5565, -6.1162) -> (29.5565, -5.1172)
  line L671 (29.5565, -5.1172) -> (30.3559, -5.1172)
  line L672 (30.3559, -5.1172) -> (30.3559, -2.0166)
  line L673 (30.3559, -2.0166) -> (29.5565, -2.0166)
  line L674 (29.5565, -2.0166) -> (29.5565, 3.7834)
  line L675 (29.5565, 3.7834) -> (30.3559, 3.7834)
  line L676 (30.3559, 3.7834) -> (30.3559, 6.8826)
  line L677 (30.3559, 6.8826) -> (29.5565, 6.8826)
  line L678 (29.5565, 6.8826) -> (29.5565, 7.8831)
  line L679 (29.5565, 7.8831) -> (15.5572, 7.8831)
  line L680 (34.6072, 7.8831) -> (34.6072, 6.8826)
  line L681 (34.6072, 6.8826) -> (33.8064, 6.8826)
  line L682 (33.8064, 6.8826) -> (33.8064, 3.7834)
  line L683 (33.8064, 3.7834) -> (34.6072, 3.7834)
  line L684 (34.6072, 3.7834) -> (34.6072, -2.0166)
  line L685 (34.6072, -2.0166) -> (33.8064, -2.0166)
  line L686 (33.8064, -2.0166) -> (33.8064, -5.1172)
  line L687 (33.8064, -5.1172) -> (34.6072, -5.1172)
  line L688 (34.6072, -5.1172) -> (34.6072, -6.1162)
  line L689 (34.6072, -6.1162) -> (48.607, -6.1162)
  line L690 (48.607, -6.1162) -> (48.607, -5.1172)
  line L691 (48.607, -5.1172) -> (49.406, -5.1172)
  line L692 (49.406, -5.1172) -> (49.406, -2.0166)
  line L693 (49.406, -2.0166) -> (48.607, -2.0166)
  line L694 (48.607, -2.0166) -> (48.607, 3.7834)
  line L695 (48.607, 3.7834) -> (49.406, 3.7834)
  line L696 (49.406, 3.7834) -> (49.406, 6.8826)
  line L697 (49.406, 6.8826) -> (48.607, 6.8826)
  line L698 (48.607, 6.8826) -> (48.607, 7.8831)
  line L699 (48.607, 7.8831) -> (34.6072, 7.8831)
  line L700 (53.657, 7.8831) -> (53.657, 6.8826)
  line L701 (53.657, 6.8826) -> (52.856, 6.8826)
  line L702 (52.856, 6.8826) -> (52.856, 3.7834)
  line L703 (52.856, 3.7834) -> (53.657, 3.7834)
  line L704 (53.657, 3.7834) -> (53.657, -2.0166)
  line L705 (53.657, -2.0166) -> (52.856, -2.0166)
  line L706 (52.856, -2.0166) -> (52.856, -5.1172)
  line L707 (52.856, -5.1172) -> (53.657, -5.1172)
  line L708 (53.657, -5.1172) -> (53.657, -6.1162)
  line L709 (53.657, -6.1162) -> (67.657, -6.1162)
  line L710 (67.657, -6.1162) -> (67.657, -5.1172)
  line L711 (67.657, -5.1172) -> (68.456, -5.1172)
  line L712 (68.456, -5.1172) -> (68.456, -2.0166)
  line L713 (68.456, -2.0166) -> (67.657, -2.0166)
  line L714 (67.657, -2.0166) -> (67.657, 3.7834)
  line L715 (67.657, 3.7834) -> (68.456, 3.7834)
  line L716 (68.456, 3.7834) -> (68.456, 6.8826)
  line L717 (68.456, 6.8826) -> (67.657, 6.8826)
  line L718 (67.657, 6.8826) -> (67.657, 7.8831)
  line L719 (67.657, 7.8831) -> (53.657, 7.8831)
  line L720 (72.707, 7.8831) -> (72.707, 6.8826)
  line L721 (72.707, 6.8826) -> (71.906, 6.8826)
  line L722 (71.906, 6.8826) -> (71.906, 3.7834)
  line L723 (71.906, 3.7834) -> (72.707, 3.7834)
  line L724 (72.707, 3.7834) -> (72.707, -2.0166)
  line L725 (72.707, -2.0166) -> (71.906, -2.0166)
  line L726 (71.906, -2.0166) -> (71.906, -5.1172)
  line L727 (71.906, -5.1172) -> (72.707, -5.1172)
  line L728 (72.707, -5.1172) -> (72.707, -6.1162)
  line L729 (72.707, -6.1162) -> (86.707, -6.1162)
  line L730 (86.707, -6.1162) -> (86.707, -5.1172)
  line L731 (86.707, -5.1172) -> (87.506, -5.1172)
  line L732 (87.506, -5.1172) -> (87.506, -2.0166)
  line L733 (87.506, -2.0166) -> (86.707, -2.0166)
  line L734 (86.707, -2.0166) -> (86.707, 3.7834)
  line L735 (86.707, 3.7834) -> (87.506, 3.7834)
  line L736 (87.506, 3.7834) -> (87.506, 6.8826)
  line L737 (87.506, 6.8826) -> (86.707, 6.8826)
  line L738 (86.707, 6.8826) -> (86.707, 7.8831)
  line L739 (86.707, 7.8831) -> (72.707, 7.8831)
  line L740 (91.757, 7.8831) -> (91.757, 6.8826)
  line L741 (91.757, 6.8826) -> (90.956, 6.8826)
  line L742 (90.956, 6.8826) -> (90.956, 3.7834)
  line L743 (90.956, 3.7834) -> (91.757, 3.7834)
  line L744 (91.757, 3.7834) -> (91.757, -2.0166)
  line L745 (91.757, -2.0166) -> (90.956, -2.0166)
  line L746 (90.956, -2.0166) -> (90.956, -5.1172)
  line L747 (90.956, -5.1172) -> (91.757, -5.1172)
  line L748 (91.757, -5.1172) -> (91.757, -6.1162)
  line L749 (91.757, -6.1162) -> (105.757, -6.1162)
  line L750 (105.757, -6.1162) -> (105.757, -5.1172)
  line L751 (105.757, -5.1172) -> (106.556, -5.1172)
  line L752 (106.556, -5.1172) -> (106.556, -2.0166)
  line L753 (106.556, -2.0166) -> (105.757, -2.0166)
  line L754 (105.757, -2.0166) -> (105.757, 3.7834)
  line L755 (105.757, 3.7834) -> (106.556, 3.7834)
  line L756 (106.556, 3.7834) -> (106.556, 6.8826)
  line L757 (106.556, 6.8826) -> (105.757, 6.8826)
  line L758 (105.757, 6.8826) -> (105.757, 7.8831)
  line L759 (105.757, 7.8831) -> (91.757, 7.8831)
  line L760 (110.807, 7.8831) -> (110.807, 6.8826)
  line L761 (110.807, 6.8826) -> (110.006, 6.8826)
  line L762 (110.006, 6.8826) -> (110.006, 3.7834)
  line L763 (110.006, 3.7834) -> (110.807, 3.7834)
  line L764 (110.807, 3.7834) -> (110.807, -2.0166)
  line L765 (110.807, -2.0166) -> (110.006, -2.0166)
  line L766 (110.006, -2.0166) -> (110.006, -5.1172)
  line L767 (110.006, -5.1172) -> (110.807, -5.1172)
  line L768 (110.807, -5.1172) -> (110.807, -6.1162)
  line L769 (110.807, -6.1162) -> (124.807, -6.1162)
  line L770 (124.807, -6.1162) -> (124.807, -5.1172)
  line L771 (124.807, -5.1172) -> (125.606, -5.1172)
  line L772 (125.606, -5.1172) -> (125.606, -2.0166)
  line L773 (125.606, -2.0166) -> (124.807, -2.0166)
  line L774 (124.807, -2.0166) -> (124.807, 3.7834)
  line L775 (124.807, 3.7834) -> (125.606, 3.7834)
  line L776 (125.606, 3.7834) -> (125.606, 6.8826)
  line L777 (125.606, 6.8826) -> (124.807, 6.8826)
  line L778 (124.807, 6.8826) -> (124.807, 7.8831)
  line L779 (124.807, 7.8831) -> (110.807, 7.8831)
  line L780 (129.857, 7.8831) -> (129.857, 6.8826)
  line L781 (129.857, 6.8826) -> (129.056, 6.8826)
  line L782 (129.056, 6.8826) -> (129.056, 3.7834)
  line L783 (129.056, 3.7834) -> (129.857, 3.7834)
  line L784 (129.857, 3.7834) -> (129.857, -2.0166)
  line L785 (129.857, -2.0166) -> (129.056, -2.0166)
  line L786 (129.056, -2.0166) -> (129.056, -5.1172)
  line L787 (129.056, -5.1172) -> (129.857, -5.1172)
  line L788 (129.857, -5.1172) -> (129.857, -6.1162)
  line L789 (129.857, -6.1162) -> (143.857, -6.1162)
  line L790 (143.857, -6.1162) -> (143.857, -5.1172)
  line L791 (143.857, -5.1172) -> (144.656, -5.1172)
  line L792 (144.656, -5.1172) -> (144.656, -2.0166)
  line L793 (144.656, -2.0166) -> (143.857, -2.0166)
  line L794 (143.857, -2.0166) -> (143.857, 3.7834)
  line L795 (143.857, 3.7834) -> (144.656, 3.7834)
  line L796 (144.656, 3.7834) -> (144.656, 6.8826)
  line L797 (144.656, 6.8826) -> (143.857, 6.8826)
  line L798 (143.857, 6.8826) -> (143.857, 7.8831)
  line L799 (143.857, 7.8831) -> (129.857, 7.8831)
  line L800 (148.907, 7.8831) -> (148.907, 6.8826)
  line L801 (148.907, 6.8826) -> (148.106, 6.8826)
  line L802 (148.106, 6.8826) -> (148.106, 3.7834)
  line L803 (148.106, 3.7834) -> (148.907, 3.7834)
  line L804 (148.907, 3.7834) -> (148.907, -2.0166)
  line L805 (148.907, -2.0166) -> (148.106, -2.0166)
  line L806 (148.106, -2.0166) -> (148.106, -5.1172)
  line L807 (148.106, -5.1172) -> (148.907, -5.1172)
  line L808 (148.907, -5.1172) -> (148.907, -6.1162)
  line L809 (148.907, -6.1162) -> (162.907, -6.1162)
  line L810 (162.907, -6.1162) -> (162.907, -5.1172)
  line L811 (162.907, -5.1172) -> (163.706, -5.1172)
  line L812 (163.706, -5.1172) -> (163.706, -2.0166)
  line L813 (163.706, -2.0166) -> (162.907, -2.0166)
  line L814 (162.907, -2.0166) -> (162.907, 3.7834)
  line L815 (162.907, 3.7834) -> (163.706, 3.7834)
  line L816 (163.706, 3.7834) -> (163.706, 6.8826)
  line L817 (163.706, 6.8826) -> (162.907, 6.8826)
  line L818 (162.907, 6.8826) -> (162.907, 7.8831)
  line L819 (162.907, 7.8831) -> (148.907, 7.8831)
  line L820 (167.957, 7.8831) -> (167.957, 6.8826)
  line L821 (167.957, 6.8826) -> (167.156, 6.8826)
  line L822 (167.156, 6.8826) -> (167.156, 3.7834)
  line L823 (167.156, 3.7834) -> (167.957, 3.7834)
  line L824 (167.957, 3.7834) -> (167.957, -2.0166)
  line L825 (167.957, -2.0166) -> (167.156, -2.0166)
  line L826 (167.156, -2.0166) -> (167.156, -5.1172)
  line L827 (167.156, -5.1172) -> (167.957, -5.1172)
  line L828 (167.957, -5.1172) -> (167.957, -6.1162)
  line L829 (167.957, -6.1162) -> (181.957, -6.1162)
  line L830 (181.957, -6.1162) -> (181.957, -5.1172)
  line L831 (181.957, -5.1172) -> (182.756, -5.1172)
  line L832 (182.756, -5.1172) -> (182.756, -2.0166)
  line L833 (182.756, -2.0166) -> (181.957, -2.0166)
  line L834 (181.957, -2.0166) -> (181.957, 3.7834)
  line L835 (181.957, 3.7834) -> (182.756, 3.7834)
  line L836 (182.756, 3.7834) -> (182.756, 6.8826)
  line L837 (182.756, 6.8826) -> (181.957, 6.8826)
  line L838 (181.957, 6.8826) -> (181.957, 7.8831)
  line L839 (181.957, 7.8831) -> (167.957, 7.8831)
  line L840 (229.87, 7.8831) -> (229.87, 6.8826)
  line L841 (229.87, 6.8826) -> (229.069, 6.8826)
  line L842 (229.069, 6.8826) -> (229.069, 3.7834)
  line L843 (229.069, 3.7834) -> (229.87, 3.7834)
  line L844 (229.87, 3.7834) -> (229.87, -2.0166)
  line L845 (229.87, -2.0166) -> (229.069, -2.0166)
  line L846 (229.069, -2.0166) -> (229.069, -5.1172)
  line L847 (229.069, -5.1172) -> (229.87, -5.1172)
  line L848 (229.87, -5.1172) -> (229.87, -6.1162)
  line L849 (229.87, -6.1162) -> (243.869, -6.1162)
  line L850 (243.869, -6.1162) -> (243.869, -5.1172)
  line L851 (243.869, -5.1172) -> (244.67, -5.1172)
  line L852 (244.67, -5.1172) -> (244.67, -2.0166)
  line L853 (244.67, -2.0166) -> (243.869, -2.0166)
  line L854 (243.869, -2.0166) -> (243.869, 3.7834)
  line L855 (243.869, 3.7834) -> (244.67, 3.7834)
  line L856 (244.67, 3.7834) -> (244.67, 6.8826)
  line L857 (244.67, 6.8826) -> (243.869, 6.8826)
  line L858 (243.869, 6.8826) -> (243.869, 7.8831)
  line L859 (243.869, 7.8831) -> (229.87, 7.8831)
  line L860 (-51.1178, 26.9331) -> (-51.1178, 25.9326)
  line L861 (-51.1178, 25.9326) -> (-51.9185, 25.9326)
  line L862 (-51.9185, 25.9326) -> (-51.9185, 22.8334)
  line L863 (-51.9185, 22.8334) -> (-51.1178, 22.8334)
  line L864 (-51.1178, 22.8334) -> (-51.1178, 17.0334)
  line L865 (-51.1178, 17.0334) -> (-51.9185, 17.0334)
  line L866 (-51.9185, 17.0334) -> (-51.9185, 13.9328)
  line L867 (-51.9185, 13.9328) -> (-51.1178, 13.9328)
  line L868 (-51.1178, 13.9328) -> (-51.1178, 12.9338)
  line L869 (-51.1178, 12.9338) -> (-37.1183, 12.9338)
  line L870 (-37.1183, 12.9338) -> (-37.1183, 13.9328)
  line L871 (-37.1183, 13.9328) -> (-36.3191, 13.9328)
  line L872 (-36.3191, 13.9328) -> (-36.3191, 17.0334)
  line L873 (-36.3191, 17.0334) -> (-37.1183, 17.0334)
  line L874 (-37.1183, 17.0334) -> (-37.1183, 22.8334)
  line L875 (-37.1183, 22.8334) -> (-36.3191, 22.8334)
  line L876 (-36.3191, 22.8334) -> (-36.3191, 25.9326)
  line L877 (-36.3191, 25.9326) -> (-37.1183, 25.9326)
  line L878 (-37.1183, 25.9326) -> (-37.1183, 26.9331)
  line L879 (-37.1183, 26.9331) -> (-51.1178, 26.9331)
  line L880 (-27.3053, 26.9331) -> (-27.3053, 25.9326)
  line L881 (-27.3053, 25.9326) -> (-28.106, 25.9326)
  line L882 (-28.106, 25.9326) -> (-28.106, 22.8334)
  line L883 (-28.106, 22.8334) -> (-27.3053, 22.8334)
  line L884 (-27.3053, 22.8334) -> (-27.3053, 17.0334)
  line L885 (-27.3053, 17.0334) -> (-28.106, 17.0334)
  line L886 (-28.106, 17.0334) -> (-28.106, 13.9328)
  line L887 (-28.106, 13.9328) -> (-27.3053, 13.9328)
  line L888 (-27.3053, 13.9328) -> (-27.3053, 12.9338)
  line L889 (-27.3053, 12.9338) -> (-13.306, 12.9338)
  line L890 (-13.306, 12.9338) -> (-13.306, 13.9328)
  line L891 (-13.306, 13.9328) -> (-12.5052, 13.9328)
  line L892 (-12.5052, 13.9328) -> (-12.5052, 17.0334)
  line L893 (-12.5052, 17.0334) -> (-13.306, 17.0334)
  line L894 (-13.306, 17.0334) -> (-13.306, 22.8334)
  line L895 (-13.306, 22.8334) -> (-12.5052, 22.8334)
  line L896 (-12.5052, 22.8334) -> (-12.5052, 25.9326)
  line L897 (-12.5052, 25.9326) -> (-13.306, 25.9326)
  line L898 (-13.306, 25.9326) -> (-13.306, 26.9331)
  line L899 (-13.306, 26.9331) -> (-27.3053, 26.9331)
  line L900 (-8.2553, 26.9331) -> (-8.2553, 25.9326)
  line L901 (-8.2553, 25.9326) -> (-9.0561, 25.9326)
  line L902 (-9.0561, 25.9326) -> (-9.0561, 22.8334)
  line L903 (-9.0561, 22.8334) -> (-8.2553, 22.8334)
  line L904 (-8.2553, 22.8334) -> (-8.2553, 17.0334)
  line L905 (-8.2553, 17.0334) -> (-9.0561, 17.0334)
  line L906 (-9.0561, 17.0334) -> (-9.0561, 13.9328)
  line L907 (-9.0561, 13.9328) -> (-8.2553, 13.9328)
  line L908 (-8.2553, 13.9328) -> (-8.2553, 12.9338)
  line L909 (-8.2553, 12.9338) -> (5.744, 12.9338)
  line L910 (5.744, 12.9338) -> (5.744, 13.9328)
  line L911 (5.744, 13.9328) -> (6.5448, 13.9328)
  line L912 (6.5448, 13.9328) -> (6.5448, 17.0334)
  line L913 (6.5448, 17.0334) -> (5.744, 17.0334)
  line L914 (5.744, 17.0334) -> (5.744, 22.8334)
  line L915 (5.744, 22.8334) -> (6.5448, 22.8334)
  line L916 (6.5448, 22.8334) -> (6.5448, 25.9326)
  line L917 (6.5448, 25.9326) -> (5.744, 25.9326)
  line L918 (5.744, 25.9326) -> (5.744, 26.9331)
  line L919 (5.744, 26.9331) -> (-8.2553, 26.9331)
  line L920 (10.7947, 26.9331) -> (10.7947, 25.9326)
  line L921 (10.7947, 25.9326) -> (9.9939, 25.9326)
  line L922 (9.9939, 25.9326) -> (9.9939, 22.8334)
  line L923 (9.9939, 22.8334) -> (10.7947, 22.8334)
  line L924 (10.7947, 22.8334) -> (10.7947, 17.0334)
  line L925 (10.7947, 17.0334) -> (9.9939, 17.0334)
  line L926 (9.9939, 17.0334) -> (9.9939, 13.9328)
  line L927 (9.9939, 13.9328) -> (10.7947, 13.9328)
  line L928 (10.7947, 13.9328) -> (10.7947, 12.9338)
  line L929 (10.7947, 12.9338) -> (24.794, 12.9338)
  line L930 (24.794, 12.9338) -> (24.794, 13.9328)
  line L931 (24.794, 13.9328) -> (25.5948, 13.9328)
  line L932 (25.5948, 13.9328) -> (25.5948, 17.0334)